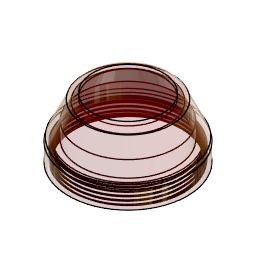
PiggySat_housing (Autodesk Fusion 360 archive; units mm, degrees)
design "PiggySat_cap"
part number: 2026-08-13-00-39-11-568
Autodesk Fusion 360 part; units mm, degrees
sketch "Sketch1" plane through (0, 0, 0) normal (0, 1, 0) x (1, 0, 0)
  line L0 (0, 0) -> (0, -29) construction
  line L1 (0, -29) -> (18.2289, -29)
  line L2 (20.9479, -27.2679) -> (28.7189, -10.6028)
  line L3 (29, -9.3349) -> (29, 0)
  line L4 (0, 0) -> (29, 0) construction
  arc A0 (18.2289, -29) -> (20.9479, -27.2679) centre (18.2289, -26) ccw
  arc A1 (28.7189, -10.6028) -> (29, -9.3349) centre (26, -9.3349) ccw
  line L5 (0, -31) -> (18.2289, -31)
  arc A2 (18.2289, -31) -> (22.7605, -28.1131) centre (18.2289, -26) ccw
  line L6 (22.7605, -28.1131) -> (30.5315, -11.448)
  arc A3 (30.5315, -11.448) -> (31, -9.3349) centre (26, -9.3349) ccw
  line L7 (31, -9.3349) -> (31, 0)
  line L8 (0, -29) -> (0, -31)
  line L9 (29, 0) -> (31, 0)
  line L10 (28.8726, -10.2) -> (25, -10.2)
  line L11 (25, -10.2) -> (25, -18.578)
  point P0 (29, -10)
  dimension "d1" = 29
  dimension "d2" = 29
  dimension "d3" = 65
  dimension "d4" = 10
  dimension "d5" = 3
  dimension "d6" = 3
  dimension "d7" = 2
  dimension "d11" = 10.2
  dimension "d12" = 4
  constraint coincident L0.start L4.start
  constraint vertical L0
  constraint perpendicular L0 L1
  constraint parallel L0 L3
  constraint horizontal L4
  constraint tangent L1 A0
  constraint tangent L2 A0
  constraint coincident P0 L2
  constraint coincident P0 L3
  constraint tangent L2 A1
  constraint tangent L3 A1
  constraint perpendicular L5 L8
  constraint perpendicular L7 L9
  constraint coincident A1 L10.start
  constraint horizontal L10
  constraint coincident L2 L11.end
  constraint perpendicular L10 L11
  measures "d1" distance of L0 L3
  measures "d2" distance of L0.start L0.end
  measures "d3" angle of L1 L2
  measures "d4" distance of P0 L3.end
  measures "d5" radius of A0
  measures "d6" radius of A1
  measures "d11" distance of L4 L10
  measures "d12" distance of L3 L11
revolve "Revolve1" add sketch "Sketch1" angle 360 about axis through (0, 0, 0) along (0, 0, 1)
thread "Thread1" "ISO Metric profile 58.0 M58x2 M58x2 6H" major diameter 58.2623 minor diameter 56.0224 pitch 2 angle 60 modelled right hand crest width 0.5401 on face at (28.8559, -2.8875, 3.1116) crest through (28.0112, 0, 0.5)
equation "d1 = ( 58 / 2 ) * 1 mm"

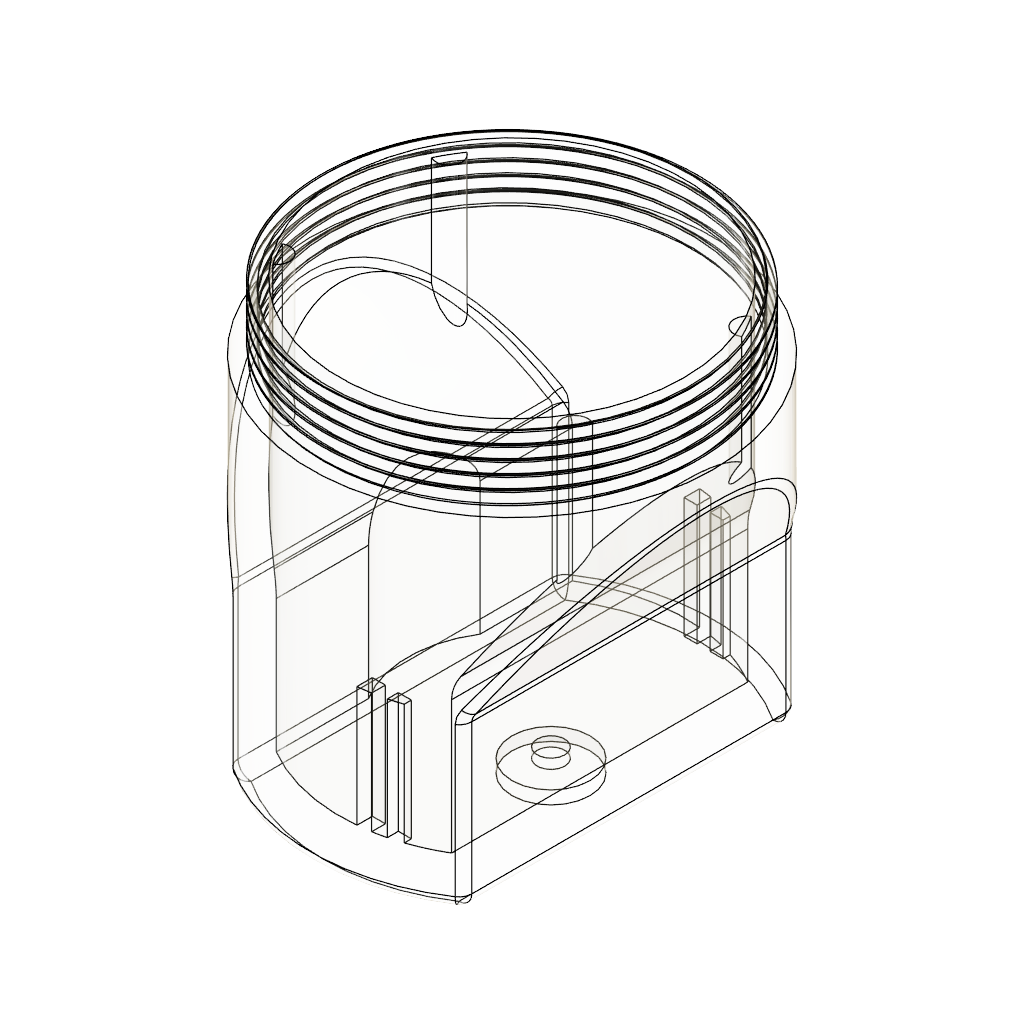
design "PiggySat_body"
part number: 2026-08-13-22-15-45-788
Autodesk Fusion 360 part; units mm, degrees
sketch "Sketch1" plane through (0, 0, 0) normal (0, 0, 1) x (1, 0, 0)
  circle A0 centre (0, 0) radius 31
  circle A1 centre (0, 0) radius 29
  circle A2 centre (0, 0) radius 26.5 construction
  circle A3 centre (-22.9497, -13.25) radius 2
  line L0 (-22.9497, -13.25) -> (0, 0) construction
  line L1 (0, 0) -> (-31, 0) construction
  line L2 (0, 0) -> (0, 31) construction
  circle A4 centre (-22.9497, 13.25) radius 2
  circle A5 centre (22.9497, 13.25) radius 2
  circle A6 centre (22.9497, -13.25) radius 2
  line L3 (2.5, 27) -> (4.5, 27)
  line L4 (4.5, 27) -> (4.5, 24)
  line L5 (4.5, 24) -> (2.5, 24)
  line L6 (2.5, 24) -> (2.5, 27)
  line L7 (8.5, 27) -> (6.5, 27)
  line L8 (6.5, 27) -> (6.5, 24)
  line L9 (6.5, 24) -> (8.5, 24)
  line L10 (8.5, 24) -> (8.5, 27)
  line L11 (4.5, 27) -> (6.5, 27) construction
  line L12 (4.5, 24) -> (6.5, 24) construction
  line L13 (2.5, -24) -> (2.5, -27)
  line L14 (2.5, -27) -> (4.5, -27)
  line L15 (4.5, -27) -> (4.5, -24)
  line L16 (4.5, -24) -> (2.5, -24)
  line L17 (6.5, -27) -> (6.5, -24)
  line L18 (8.5, -27) -> (6.5, -27)
  line L19 (8.5, -24) -> (8.5, -27)
  line L20 (6.5, -24) -> (8.5, -24)
  arc A7 (0, 16) -> (0, -16) centre (0, 0) ccw
  line L21 (0, 16) -> (0, -16)
  line L22 (0, 0) -> (6, 0) construction
  circle A8 centre (6, 0) radius 2.125
  circle A9 centre (6, 0) radius 6
  dimension "d1" = 62
  dimension "d16" = 58
  dimension "d19" = 53
  dimension "d20" = 4
  dimension "d21" = 30
  dimension "d25" = 2
  dimension "d26" = 2
  dimension "d27" = 2
  dimension "d28" = 3
  dimension "d29" = 7
  dimension "d30" = 2.5
  dimension "d50" = 16
  dimension "d60" = 12
  dimension "d61" = 4.25
  dimension "d62" = 6
  constraint coincident A0.centre A1.centre
  constraint concentric A0 A2
  constraint coincident A2 A3.centre
  constraint coincident A3.centre L0.start
  constraint coincident A0 L1.end
  constraint horizontal L1
  constraint coincident A0 L2.end
  constraint vertical L2
  constraint symmetric A3 L1 A4
  constraint symmetric A3 L2 A6
  constraint symmetric L2 A4 A5
  constraint horizontal L3
  constraint vertical L4
  constraint horizontal L5
  constraint vertical L6
  constraint horizontal L7
  constraint vertical L8
  constraint horizontal L9
  constraint vertical L10
  constraint perpendicular L8 L11
  constraint perpendicular L8 L12
  constraint symmetric L1 L3.start L13.end
  constraint symmetric L1 L3.end L14.end
  constraint symmetric L1 L4.end L15.end
  constraint symmetric L1 L5.end L13.start
  constraint symmetric L1 L7.start L18.start
  constraint symmetric L1 L7.end L17.start
  constraint symmetric L1 L8.end L17.end
  constraint symmetric L1 L9.end L19.start
  constraint coincident L2 A7.start
  constraint perpendicular A7 L21
  constraint perpendicular L2 L22
  constraint coincident L22.end A8.centre
  constraint concentric A8 A9
  measures "d1" diameter of A0
  measures "d16" diameter of A1
  measures "d19" diameter of A2
  measures "d20" diameter of A3
  measures "d21" angle of L0 L1
  measures "d25" distance of L3.start L3.end
  measures "d26" distance of L3.end L7.end
  measures "d27" distance of L7.start L7.end
  measures "d28" distance of L7.start L9.end
  measures "d29" distance of L2.end L5
  measures "d30" distance of L2 L6
  measures "d50" radius of A7
  measures "d60" diameter of A9
  measures "d61" diameter of A8
  measures "d62" distance of A0.centre L22.end
sketch "Sketch2" plane through (0, 0, 0) normal (0, 1, 0) x (1, 0, 0)
  line L0 (0, 0) -> (-31, 0)
  line L1 (-31, 0) -> (-31, 15)
  line L2 (-31, 15) -> (-18, 37.5167)
  line L3 (-18, 37.5167) -> (-18, 63)
  line L4 (-18, 63) -> (0, 63)
  line L5 (0, 63) -> (0, 0) construction
  line L6 (-31, 15) -> (-31, 63)
  line L7 (-31, 63) -> (-18, 63)
  line L8 (31, 63) -> (18, 63)
  line L9 (18, 37.5167) -> (18, 63)
  line L10 (31, 15) -> (18, 37.5167)
  line L11 (31, 15) -> (31, 63)
  dimension "d2" = 18
  dimension "d3" = 15
  dimension "d4" = 30
  dimension "d5" = 31
  dimension "d6" = 63
  constraint coincident L0.start L5.end
  constraint horizontal L0
  constraint perpendicular L0 L1
  constraint perpendicular L0 L3
  constraint perpendicular L3 L4
  constraint perpendicular L0 L5
  constraint parallel L1 L6
  constraint perpendicular L3 L7
  constraint symmetric L1.end L5 L10.start
  constraint symmetric L2.end L5 L9.start
  constraint symmetric L3.end L5 L8.end
  constraint symmetric L5 L6.end L8.start
  measures "d2" distance of L3.end L4.end
  measures "d3" distance of L0.end L1.end
  measures "d4" angle of L1 L2
  measures "d5" distance of L1 L5
  measures "d6" distance of L0.start L4.end
extrude "Extrude1" add sketch "Sketch1" against normal blind 63 contours A0 | A1 | A3 | A4 | A5 | A6 | L3 L4 L5 L6 | L7 L8 L9 L10 | L13 L14 L15 L16 | L17 L18 L19 L20 | A7 L21 | A9 | A8
extrude "Extrude2" cut sketch "Sketch2" along normal through all and the other way through all
fillet "Fillet1" radius 2 5 faces at (20.002, -7.9482, -34.0492) (18, 8.413, -54.5056) (3.4867, -10.5002, -63) (-18, 8.413, -54.5056) (-20.002, -7.9482, -34.0492)
shell "Shell1" thickness 4.5 removed faces 1 at (5.5348, -2.0554, 0)
extrude "Extrude4" add sketch "Sketch1" against normal blind 22 from surface at -1.6 contours A3 | A4 | A5 | A6
extrude "Extrude5" add sketch "Sketch1" against normal up to surface (18.5 mm away) from surface at -40 contours L3 L4 L5 L6 | L7 L8 L9 L10 | L13 L14 L15 L16 | L17 L18 L19 L20
extrude "Extrude3" cut sketch "Sketch1" against normal blind 10 contours A0
thread "Thread1" "ISO Metric profile 58.0 M58x2 M58x2 6g" major diameter 57.822 minor diameter 55.5239 pitch 2 angle 60 modelled right hand crest width 0.2789 on face at (28.8559, -2.8875, -3.3333) crest through (28.911, 0, 0.5)
extrude "Extrude7" cut sketch "Sketch1" along normal blind 2 from surface at -63 contours A9 | A8
extrude "Extrude8" cut sketch "Sketch1" along normal blind 1.5 from surface at -61 contours A8
extrude "Extrude9" cut sketch "Sketch1" against normal up to surface (58.5 mm away) contours A7 L21
